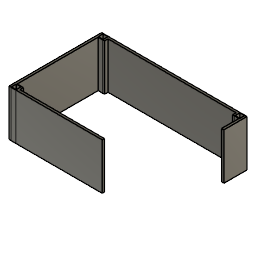
Old Dumping Container (Autodesk Fusion 360 design; units mm, degrees)
Autodesk Fusion 360 part; units mm, degrees
sketch "Sketch3" plane through (0, 0, 0) normal (0, 0, 1) x (1, 0, 0)
  line L0 (7.1438, 0.7938) -> (2.3813, 0.7938)
  line L1 (2.3813, 0.7938) -> (2.3813, 5.5563)
  line L2 (2.3813, 5.5563) -> (7.1438, 5.5563)
  line L3 (7.1438, 5.5563) -> (7.1438, 0.7938)
  line L4 (7.1438, 96.0438) -> (2.3813, 96.0438)
  line L5 (2.3813, 96.0438) -> (2.3813, 100.8063)
  line L6 (2.3813, 100.8063) -> (7.1438, 100.8063)
  line L7 (7.1438, 100.8063) -> (7.1438, 96.0438)
  line L8 (9.525, 0) -> (0, 0)
  line L9 (0, 0) -> (0, 6.35)
  line L10 (0, 6.35) -> (9.525, 6.35)
  line L11 (9.525, 6.35) -> (9.525, 0)
  line L12 (9.525, 95.25) -> (0, 95.25)
  line L13 (0, 95.25) -> (0, 101.6)
  line L14 (0, 101.6) -> (9.525, 101.6)
  line L15 (9.525, 101.6) -> (9.525, 95.25)
  line L16 (2.1273, 5.8103) -> (7.3977, 5.8103)
  line L17 (7.3977, 5.8103) -> (7.3977, 0.5398)
  line L18 (7.3977, 0.5398) -> (2.1273, 0.5398)
  line L19 (2.1273, 0.5398) -> (2.1273, 5.8103)
  line L20 (7.3977, 101.0603) -> (7.3977, 95.7897)
  line L21 (7.3977, 95.7897) -> (2.1273, 95.7897)
  line L22 (2.1273, 95.7897) -> (2.1273, 101.0603)
  line L23 (2.1273, 101.0603) -> (7.3977, 101.0603)
  line L24 (159.385, 0) -> (149.86, 0)
  line L25 (152.2413, 96.0438) -> (152.2413, 100.8063)
  line L26 (152.2413, 5.5563) -> (157.0038, 5.5563)
  line L27 (159.385, 95.25) -> (149.86, 95.25)
  line L28 (159.385, 6.35) -> (159.385, 0)
  line L29 (157.2578, 5.8103) -> (157.2578, 0.5398)
  line L30 (157.0038, 5.5563) -> (157.0038, 0.7937)
  line L31 (149.86, 0) -> (149.86, 6.35)
  line L32 (157.0038, 96.0438) -> (152.2413, 96.0438)
  line L33 (152.2413, 100.8063) -> (157.0038, 100.8063)
  line L34 (157.2578, 101.0603) -> (157.2578, 95.7898)
  line L35 (151.9873, 101.0603) -> (157.2578, 101.0603)
  line L36 (159.385, 101.6) -> (159.385, 95.25)
  line L37 (157.0038, 0.7937) -> (152.2413, 0.7938)
  line L38 (157.2578, 95.7898) -> (151.9873, 95.7898)
  line L39 (157.0038, 100.8063) -> (157.0038, 96.0438)
  line L40 (149.86, 101.6) -> (159.385, 101.6)
  line L41 (157.2578, 0.5397) -> (151.9873, 0.5397)
  line L42 (149.86, 6.35) -> (159.385, 6.35)
  line L43 (151.9873, 5.8103) -> (157.2578, 5.8103)
  line L44 (149.86, 95.25) -> (149.86, 101.6)
  line L45 (151.9873, 95.7898) -> (151.9873, 101.0602)
  line L46 (152.2413, 0.7938) -> (152.2413, 5.5563)
  line L47 (151.9873, 0.5397) -> (151.9873, 5.8103)
  line L48 (149.86, 101.6) -> (9.525, 101.6)
  line L49 (9.525, 101.6) -> (9.525, 99.06)
  line L50 (9.525, 99.06) -> (149.86, 99.06)
  line L51 (149.86, 99.06) -> (149.86, 101.6)
  line L52 (159.385, 95.25) -> (156.845, 95.25)
  line L53 (156.845, 95.25) -> (156.845, 6.35)
  line L54 (156.845, 6.35) -> (159.385, 6.35)
  line L55 (159.385, 6.35) -> (159.385, 95.25)
  line L56 (149.86, 0) -> (9.525, 0)
  line L57 (9.525, 0) -> (9.525, 2.54)
  line L58 (9.525, 2.54) -> (149.86, 2.54)
  line L59 (149.86, 2.54) -> (149.86, 0)
  line L60 (0, 95.25) -> (2.54, 95.25)
  line L61 (2.54, 95.25) -> (2.54, 6.35)
  line L62 (2.54, 6.35) -> (0, 6.35)
  line L63 (0, 6.35) -> (0, 95.25)
  point P0 (149.86, 0)
  dimension "d31" = 4.7625
  dimension "d37" = 6.35
  dimension "d38" = 9.525
  dimension "d39" = 0.7937
  dimension "d40" = 2.3813
  dimension "d41" = 0.7937
  dimension "d42" = 6.35
  dimension "d43" = 2.3813
  dimension "d52" = 9.525
  dimension "d55" = -0.254
  dimension "d56" = -0.254
  dimension "d66" = 101.6
  dimension "d67" = -0.254
  dimension "d68" = -0.254
  dimension "d69" = 4.7625
  dimension "d70" = 6.35
  dimension "d71" = 9.525
  dimension "d72" = 0.7937
  dimension "d73" = 2.3813
  dimension "d74" = 0.7937
  dimension "d75" = 6.35
  dimension "d76" = 2.3813
  dimension "d77" = 9.525
  dimension "d78" = 101.6
  dimension "d79" = 145.0975
  dimension "d98" = 2.54
  dimension "d99" = 2.54
  dimension "d100" = 2.54
  dimension "d101" = 2.54
  constraint horizontal L0
  constraint vertical L1
  constraint horizontal L2
  constraint vertical L3
  constraint horizontal L4
  constraint vertical L5
  constraint horizontal L6
  constraint vertical L7
  constraint equal L4 L5
  constraint equal L1 L4
  constraint equal L0 L1
  constraint vertical L1.end L4.end
  constraint horizontal L8
  constraint vertical L9
  constraint horizontal L10
  constraint vertical L11
  constraint horizontal L12
  constraint vertical L13
  constraint horizontal L14
  constraint vertical L15
  constraint coincident L8.end L9.start
  constraint horizontal L37
  constraint vertical L46
  constraint horizontal L26
  constraint vertical L30
  constraint horizontal L32
  constraint vertical L25
  constraint horizontal L33
  constraint vertical L39
  constraint equal L25 L32
  constraint equal L32 L46
  constraint equal L37 L46
  constraint vertical L25.start L26.start
  constraint horizontal L24
  constraint vertical L31
  constraint horizontal L42
  constraint vertical L28
  constraint horizontal L27
  constraint vertical L44
  constraint horizontal L40
  constraint vertical L36
  constraint coincident P0 L24.end
  constraint horizontal L8.start P0
  constraint horizontal L48
  constraint vertical L49
  constraint horizontal L50
  constraint vertical L51
  constraint coincident L15 L49.end
  constraint horizontal L52
  constraint vertical L53
  constraint horizontal L54
  constraint vertical L55
  constraint coincident L42 L53.end
  constraint horizontal L56
  constraint vertical L57
  constraint horizontal L58
  constraint vertical L59
  constraint coincident L11 L57.end
  constraint horizontal L60
  constraint vertical L61
  constraint horizontal L62
  constraint vertical L63
  constraint coincident L10 L61.end
  measures "d31" distance of L4.end L5.end
  measures "d37" distance of L8.start L10.end
  measures "d38" distance of L8.start L8.end
  measures "d39" distance of L0 L8
  measures "d40" distance of L3 L11
  measures "d41" distance of L4 L12
  measures "d42" distance of L12.start L14.end
  measures "d43" distance of L7 L15
  measures "d52" distance of L13.end L14.end
  measures "d66" distance of L8 L14
  measures "d69" distance of L25.start L25.end
  measures "d70" distance of L28.start L24.start
  measures "d71" distance of P0 L24.start
  measures "d72" distance of L24 L37
  measures "d73" distance of L28 L30
  measures "d74" distance of L27 L32
  measures "d75" distance of L36.start L27.start
  measures "d76" distance of L36 L39
  measures "d77" distance of L36.start L40.start
  measures "d78" distance of L24 L40
  measures "d79" distance of L7 L25
  measures "d98" distance of L48 L50
  measures "d99" distance of L53 L55
  measures "d100" distance of L56 L58
  measures "d101" distance of L61 L63
extrude "Extrude4" add sketch "Sketch3" along normal blind 50.8 contours L8 L9 L10 L11 L57 L62 | L11 L31 L56 L57 L58 L59 | L24 L28 L31 L42 L54 L59 | L10 L12 L60 L61 L62 L63 | L12 L13 L14 L15 L49 L60 | L27 L42 L52 L53 L54 L55 | L27 L36 L40 L44 L51 L52 | L15 L44 L48 L49 L50 L51
sketch "Sketch6" plane through (159.385, 0, 0) normal (-1, 0, 0) x (0, -1, 0)
  line L0 (-101.6, 0) -> (0, 0)
  line L1 (0, 0) -> (0, 50.8)
  line L2 (0, 50.8) -> (-101.6, 50.8)
  line L3 (-101.6, 50.8) -> (-101.6, 0)
  line L4 (-101.6, 50.8) -> (-76.2, 50.8)
  line L5 (-76.2, 50.8) -> (-76.2, 0)
  line L6 (-76.2, 0) -> (-101.6, 0)
  line L7 (-101.6, 0) -> (-101.6, 50.8)
  line L8 (0, 0) -> (-101.6, 0)
  line L9 (-101.6, 0) -> (-101.6, 50.8)
  line L10 (-101.6, 50.8) -> (0, 50.8)
  line L11 (0, 50.8) -> (0, 0)
  dimension "d102" = 76.2
  constraint horizontal L4
  constraint vertical L5
  constraint horizontal L6
  constraint vertical L7
  constraint coincident L0 L5.end
  constraint coincident L2.end L3.start
  measures "d102" distance of L1 L5
extrude "Extrude10" cut sketch "Sketch6" along normal blind 57.15 contours L0 L1 L2 L5 L8 L10 L11
equation "d39 = ( 1 / 32 ) * 1 in"
equation "d40 = ( 3 / 32 ) * 1 in"
equation "d41 = ( 1 / 32 ) * 1 in"
equation "d43 = ( 3 / 32 ) * 1 in"
equation "d52 = ( 3 / 8 ) * 1 in"
equation "d72 = ( 1 / 32 ) * 1 in"
equation "d73 = ( 3 / 32 ) * 1 in"
equation "d74 = ( 1 / 32 ) * 1 in"
equation "d76 = ( 3 / 32 ) * 1 in"
equation "d77 = ( 3 / 8 ) * 1 in"
equation "d79 = 4.9875 in + 0.725 in"
